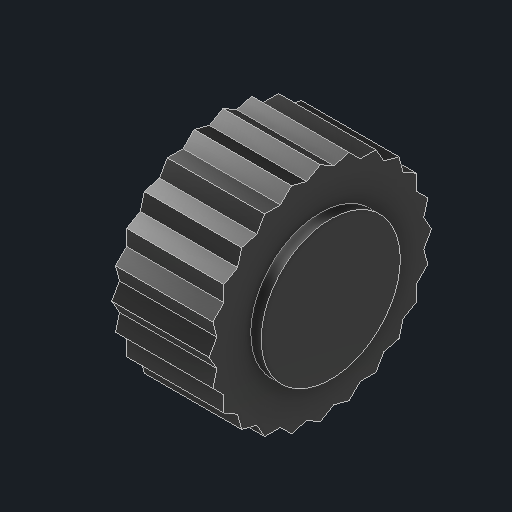
# Autodesk Inventor part: c8n_focus_knob
Saved by Autodesk Inventor 2027.1 (Build 311270010, 270A)
## iProperties
Created: 2026-11-04
Part Number: c8n_focus_knob
Material: Generic
Description: Focus knob (x2)
Document SubType Name: Modeling
Designer: Claude (from photos)
Density: 1 g/cm^3
Appearance: Glossy - Black
Author: alexg
Autodesk Inventor part; units mm, degrees
ref_plane "XZ Plane" through (0, 0, 0) normal (0, 1, 0) x (-1, 0, 0)
sketch "Pinion shaft sketch" plane through (0, 0, 0) normal (1, 0, 0) x (0, 1, 0)
  circle A0 centre (0, 0) radius 3
  constraints: 1 centre point
extrude "Pinion shaft" add sketch "Pinion shaft sketch" along normal blind 6
ref_plane "Work Plane1" through (6, 0, 0) normal (1, 0, 0) x (0, 1, 0)
sketch "Focus knob sketch" plane through (6, 0, 0) normal (1, 0, 0) x (0, 1, 0)
  line L0 (0, 16) -> (1.9579, 14.8717)
  line L1 (1.9579, 14.8717) -> (4.1411, 15.4548)
  line L2 (4.1411, 15.4548) -> (5.7403, 13.8582)
  line L3 (5.7403, 13.8582) -> (8, 13.8564)
  line L4 (8, 13.8564) -> (9.1314, 11.9003)
  line L5 (9.1314, 11.9003) -> (11.3137, 11.3137)
  line L6 (11.3137, 11.3137) -> (11.9003, 9.1314)
  line L7 (11.9003, 9.1314) -> (13.8564, 8)
  line L8 (13.8564, 8) -> (13.8582, 5.7403)
  line L9 (13.8582, 5.7403) -> (15.4548, 4.1411)
  line L10 (15.4548, 4.1411) -> (14.8717, 1.9579)
  line L11 (14.8717, 1.9579) -> (16, 0)
  line L12 (16, 0) -> (14.8717, -1.9579)
  line L13 (14.8717, -1.9579) -> (15.4548, -4.1411)
  line L14 (15.4548, -4.1411) -> (13.8582, -5.7403)
  line L15 (13.8582, -5.7403) -> (13.8564, -8)
  line L16 (13.8564, -8) -> (11.9003, -9.1314)
  line L17 (11.9003, -9.1314) -> (11.3137, -11.3137)
  line L18 (11.3137, -11.3137) -> (9.1314, -11.9003)
  line L19 (9.1314, -11.9003) -> (8, -13.8564)
  line L20 (8, -13.8564) -> (5.7403, -13.8582)
  line L21 (5.7403, -13.8582) -> (4.1411, -15.4548)
  line L22 (4.1411, -15.4548) -> (1.9579, -14.8717)
  line L23 (1.9579, -14.8717) -> (0, -16)
  line L24 (0, -16) -> (-1.9579, -14.8717)
  line L25 (-1.9579, -14.8717) -> (-4.1411, -15.4548)
  line L26 (-4.1411, -15.4548) -> (-5.7403, -13.8582)
  line L27 (-5.7403, -13.8582) -> (-8, -13.8564)
  line L28 (-8, -13.8564) -> (-9.1314, -11.9003)
  line L29 (-9.1314, -11.9003) -> (-11.3137, -11.3137)
  line L30 (-11.3137, -11.3137) -> (-11.9003, -9.1314)
  line L31 (-11.9003, -9.1314) -> (-13.8564, -8)
  line L32 (-13.8564, -8) -> (-13.8582, -5.7403)
  line L33 (-13.8582, -5.7403) -> (-15.4548, -4.1411)
  line L34 (-15.4548, -4.1411) -> (-14.8717, -1.9579)
  line L35 (-14.8717, -1.9579) -> (-16, 0)
  line L36 (-16, 0) -> (-14.8717, 1.9579)
  line L37 (-14.8717, 1.9579) -> (-15.4548, 4.1411)
  line L38 (-15.4548, 4.1411) -> (-13.8582, 5.7403)
  line L39 (-13.8582, 5.7403) -> (-13.8564, 8)
  line L40 (-13.8564, 8) -> (-11.9003, 9.1314)
  line L41 (-11.9003, 9.1314) -> (-11.3137, 11.3137)
  line L42 (-11.3137, 11.3137) -> (-9.1314, 11.9003)
  line L43 (-9.1314, 11.9003) -> (-8, 13.8564)
  line L44 (-8, 13.8564) -> (-5.7403, 13.8582)
  line L45 (-5.7403, 13.8582) -> (-4.1411, 15.4548)
  line L46 (-4.1411, 15.4548) -> (-1.9579, 14.8717)
  line L47 (-1.9579, 14.8717) -> (0, 16)
  constraints: 96 end point
extrude "Focus knob" add sketch "Focus knob sketch" along normal blind 14
ref_plane "Work Plane2" through (20, 0, 0) normal (1, 0, 0) x (0, 1, 0)
sketch "Cap sketch" plane through (20, 0, 0) normal (1, 0, 0) x (0, 1, 0)
  circle A0 centre (0, 0) radius 10
  constraints: 1 centre point
extrude "Cap" add sketch "Cap sketch" along normal blind 1.5
body "Solid1"
